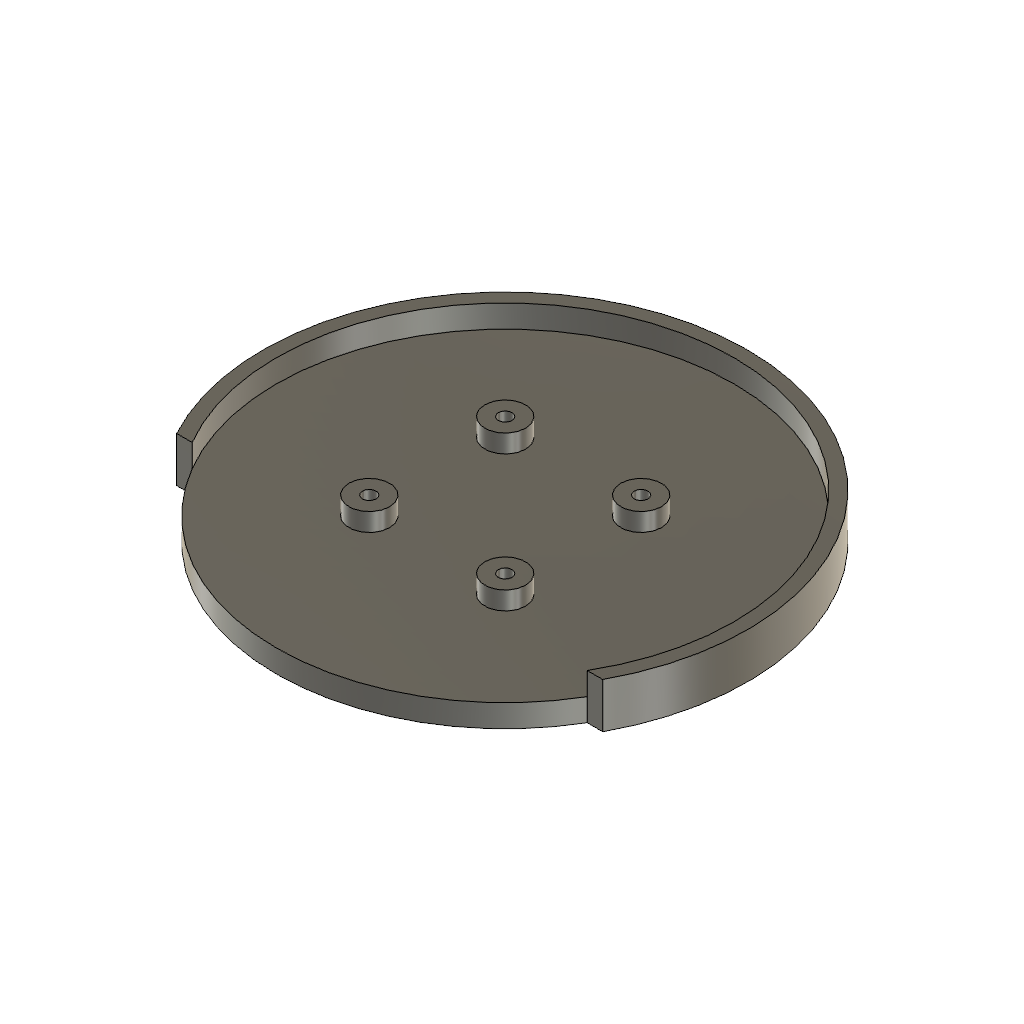
Cylinder Cover (with camera attachment) (Autodesk Fusion 360 design; units mm, degrees)
Autodesk Fusion 360 part; units mm, degrees
sketch "Sketch1" plane through (0, 0, 0) normal (0, 0, 1) x (1, 0, 0)
  circle A0 centre (0, 0) radius 50.5
  circle A1 centre (0, 0) radius 53.5
  line L0 (19, 19) -> (-19, -19) construction
  line L1 (-19, 19) -> (19, -19) construction
  circle A2 centre (-15, 15) radius 1.5
  circle A3 centre (15, 15) radius 1.5
  circle A4 centre (-15, -15) radius 1.5
  circle A5 centre (15, -15) radius 1.5
  circle A6 centre (15, -15) radius 4.5
  circle A7 centre (15, 15) radius 4.5
  circle A8 centre (-15, 15) radius 4.5
  circle A9 centre (-15, -15) radius 4.5
  line L2 (47.0876, -25.5) -> (-47.0876, -25.5)
  line L3 (-47.0876, -25.5) -> (-47.0876, -75.5)
  line L4 (-47.0876, -75.5) -> (47.0876, -75.5)
  line L5 (47.0876, -75.5) -> (47.0876, -25.5)
  line L6 (47.0876, -25.5) -> (-47.0876, -75.5) construction
  line L7 (-47.0876, -25.5) -> (47.0876, -75.5) construction
  point P0 (0, -50.5)
  dimension "d1" = 101
  dimension "d4" = 3
  dimension "d7" = 38
  dimension "d8" = 38
  dimension "d9" = 3
  dimension "d10" = 3
  dimension "d11" = 3
  dimension "d12" = 3
  dimension "d25" = 3
  dimension "d26" = 3
  dimension "d27" = 3
  dimension "d28" = 3
  dimension "d33" = 50
  constraint coincident A0.centre A1.centre
  constraint coincident L0 A0.centre
  constraint coincident L1 A0.centre
  constraint horizontal L2
  constraint perpendicular L2 L3
  constraint parallel L2 L4
  constraint parallel L3 L5
  constraint coincident L6 P0
  constraint coincident L7 P0
  constraint coincident A0 P0
  measures "d1" diameter of A0
  measures "d7" distance of L0.end L1.end
  measures "d8" distance of L1.start L0.end
  measures "d9" diameter of A2
  measures "d10" diameter of A3
  measures "d11" diameter of A4
  measures "d12" diameter of A5
  measures "d25" distance of A5
  measures "d26" distance of A3
  measures "d27" distance of A2
  measures "d28" distance of A4
  measures "d33" distance of L2.end L3.end
extrude "Extrude1" add sketch "Sketch1" against normal blind 5 contours A0 L2 | A0 L2 | A2 | A3 | A4 | A5 | A6 | A7 | A8 | A9
extrude "Extrude3" add sketch "Sketch1" along normal blind 5 and the other way blind 5 contours A0 A1 L2 picked at (-45.8239, -23.2827)
extrude "Extrude4" cut sketch "Sketch1" against normal blind 5 contours A2 | A3 | A4 | A5
extrude "Extrude5" add sketch "Sketch1" along normal blind 4 contours A6 | A7 | A8 | A9
